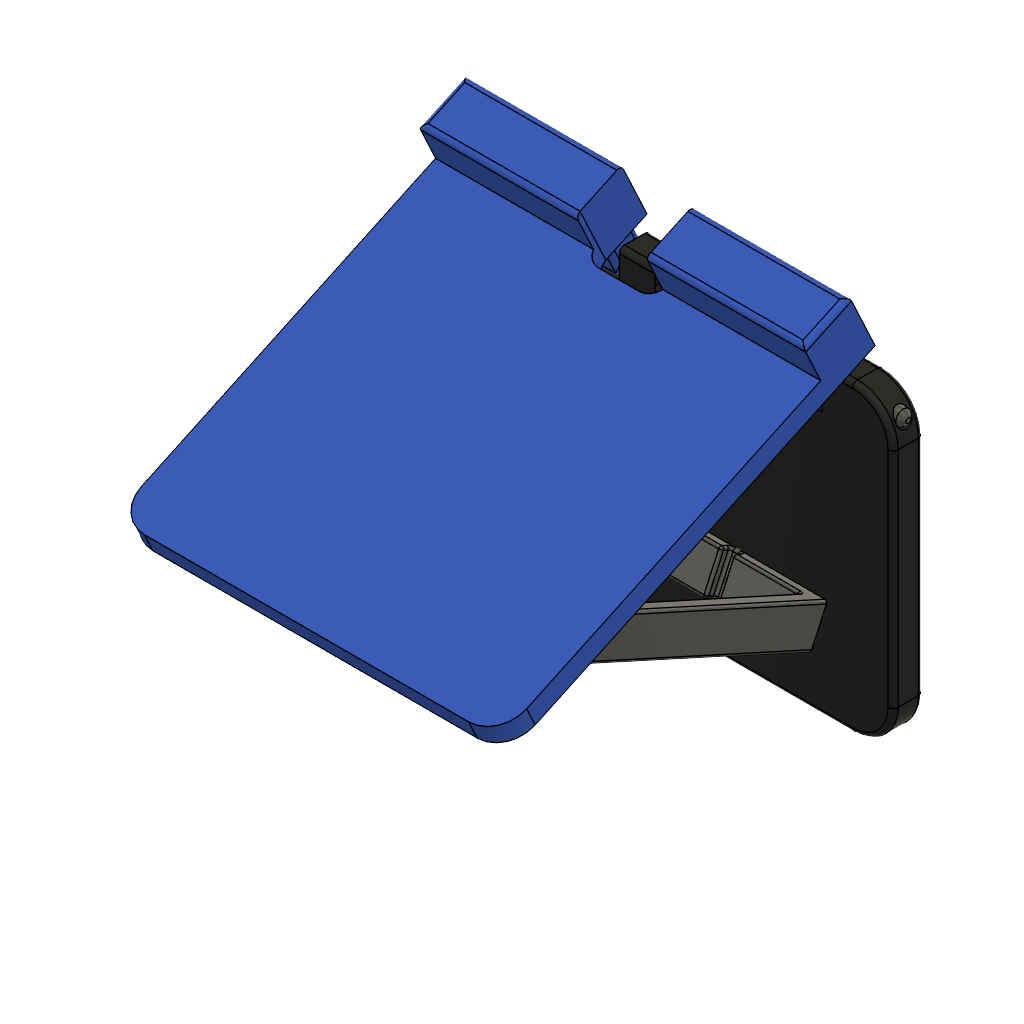
Foldable_Mobile_Stand (Autodesk Fusion 360 design; units mm, degrees)
part number: 2026-11-21-18-16-52-364
part number: 2026-11-21-19-07-08-152
part number: 2026-11-21-19-07-08-221
part number: 2026-11-21-19-07-08-273
part number: 2026-11-21-19-07-08-337
part number: 2026-11-21-19-07-08-382
Autodesk Fusion 360 part; units mm, degrees
sketch "Base Outline" plane through (0, 0, 0) normal (0, 0, 1) x (1, 0, 0)
  line L0 (0, 0) -> (80, 0)
  line L1 (80, 0) -> (80, 60)
  line L2 (80, 60) -> (0, 60)
  line L3 (0, 60) -> (0, 0)
  dimension "d9" = 80
  dimension "d10" = 60
  constraint coincident L0.start L3.end
  measures "d9" horizontal distance of L0.start L0.end
  measures "d10" vertical distance of L0.end L1.end
extrude "Base Box" add sketch "Base Outline" along normal blind 6 makes body 1
fillet "Vertical Corner Fillets" radius 8 4 edges at (0, 60, 3) (80, 60, 3) (80, 0, 3) (0, 0, 3) on bodies 1
fillet "Top Bottom Edge Fillets" radius 1 128 edges at (2.3431, 2.3431, 6) (0, 30, 6) (2.3431, 57.6569, 6) (40, 60, 6) (77.6569, 57.6569, 6) (80, 30, 6) (77.6569, 2.3431, 6) (40, 0, 6) (40, 0, 6) (77.6569, 2.3431, 6) (80, 30, 6) (77.6569, 57.6569, 6) (40, 60, 6) (2.3431, 57.6569, 6) (0, 30, 6) (2.3431, 2.3431, 6) (77.6569, 2.3431, 6) (40, 0, 6) (2.3431, 2.3431, 6) (0, 30, 6) (2.3431, 57.6569, 6) (40, 60, 6) (77.6569, 57.6569, 6) (80, 30, 6) (80, 30, 6) (77.6569, 57.6569, 6) (40, 60, 6) (2.3431, 57.6569, 6) (0, 30, 6) (2.3431, 2.3431, 6) (40, 0, 6) (77.6569, 2.3431, 6) (77.6569, 57.6569, 6) (80, 30, 6) (77.6569, 2.3431, 6) (40, 0, 6) (2.3431, 2.3431, 6) (0, 30, 6) (2.3431, 57.6569, 6) (40, 60, 6) (40, 60, 6) (2.3431, 57.6569, 6) (0, 30, 6) (2.3431, 2.3431, 6) (40, 0, 6) (77.6569, 2.3431, 6) (80, 30, 6) (77.6569, 57.6569, 6) (2.3431, 57.6569, 6) (40, 60, 6) (77.6569, 57.6569, 6) (80, 30, 6) (77.6569, 2.3431, 6) (40, 0, 6) (2.3431, 2.3431, 6) (0, 30, 6) (0, 30, 6) (2.3431, 2.3431, 6) (40, 0, 6) (77.6569, 2.3431, 6) (80, 30, 6) (77.6569, 57.6569, 6) (40, 60, 6) (2.3431, 57.6569, 6) (2.3431, 2.3431, 0) (40, 0, 0) (77.6569, 2.3431, 0) (80, 30, 0) (77.6569, 57.6569, 0) (40, 60, 0) (2.3431, 57.6569, 0) (0, 30, 0) (0, 30, 0) (2.3431, 2.3431, 0) (40, 0, 0) (77.6569, 2.3431, 0) (80, 30, 0) (77.6569, 57.6569, 0) (40, 60, 0) (2.3431, 57.6569, 0) (2.3431, 57.6569, 0) (0, 30, 0) (2.3431, 2.3431, 0) (40, 0, 0) (77.6569, 2.3431, 0) (80, 30, 0) (77.6569, 57.6569, 0) (40, 60, 0) (40, 60, 0) (2.3431, 57.6569, 0) (0, 30, 0) (2.3431, 2.3431, 0) (40, 0, 0) (77.6569, 2.3431, 0) (80, 30, 0) (77.6569, 57.6569, 0) (77.6569, 57.6569, 0) (40, 60, 0) (2.3431, 57.6569, 0) (0, 30, 0) (2.3431, 2.3431, 0) (40, 0, 0) (77.6569, 2.3431, 0) (80, 30, 0) (80, 30, 0) (77.6569, 57.6569, 0) (40, 60, 0) (2.3431, 57.6569, 0) (0, 30, 0) (2.3431, 2.3431, 0) (40, 0, 0) (77.6569, 2.3431, 0) (77.6569, 2.3431, 0) (80, 30, 0) (77.6569, 57.6569, 0) (40, 60, 0) (2.3431, 57.6569, 0) (0, 30, 0) (2.3431, 2.3431, 0) (40, 0, 0) (40, 0, 0) (77.6569, 2.3431, 0) (80, 30, 0) (77.6569, 57.6569, 0) (40, 60, 0) (2.3431, 57.6569, 0) (0, 30, 0) (2.3431, 2.3431, 0) on bodies 1
sketch "Rear Slots" plane through (0, 0, 0) normal (0, 0, 1) x (1, 0, 0)
  line L0 (14, 52) -> (26, 52)
  line L1 (26, 52) -> (26, 63)
  line L2 (26, 63) -> (14, 63)
  line L3 (14, 63) -> (14, 52)
  line L4 (54, 52) -> (66, 52)
  line L5 (66, 52) -> (66, 63)
  line L6 (66, 63) -> (54, 63)
  line L7 (54, 63) -> (54, 52)
extrude "Rear Slots Cut" cut sketch "Rear Slots" along normal through all bodies 1
sketch "Cable Notch" plane through (0, 0, 0) normal (0, 0, 1) x (1, 0, 0)
  line L0 (33, 63) -> (33, 57)
  arc A0 (33, 57) -> (36, 54) centre (36.0011, 57.0011) ccw
  line L1 (36, 54) -> (44, 54)
  arc A1 (44, 54) -> (47, 57) centre (43.9989, 57.0011) ccw
  line L2 (47, 57) -> (47, 63)
  line L3 (47, 63) -> (33, 63)
extrude "Cable Notch Cut" cut sketch "Cable Notch" along normal through all bodies 1
sketch "Hinge Pin Hole" plane through (0, 0, 0) normal (1, 0, 0) x (0, 0, -1)
  circle A0 centre (-3, 56) radius 1.6
  dimension "d19" = 3.2
  measures "d19" diameter of A0
extrude "Hinge Pin Hole Cut" cut sketch "Hinge Pin Hole" against normal through all bodies 1
sketch "Bottom Recesses" plane through (0, 0, 0) normal (0, 0, 1) x (1, 0, 0)
  circle A0 centre (12, 12) radius 5
  circle A1 centre (68, 12) radius 5
  circle A2 centre (12, 46) radius 5
  circle A3 centre (68, 46) radius 5
  dimension "d21" = 10
  dimension "d22" = 10
  dimension "d23" = 10
  dimension "d24" = 10
  measures "d21" diameter of A0
  measures "d22" diameter of A1
  measures "d23" diameter of A2
  measures "d24" diameter of A3
extrude "Bottom Recesses Cut" cut sketch "Bottom Recesses" along normal blind 1 bodies 1
ref_plane "WorkPlane1" through (0, 80, 0) normal (0, 1, 0) x (0, 0, 1)
sketch "BackSupport Plate" plane through (0, 80, 0) normal (0, 1, 0) x (1, 0, 0)
  line L0 (0, 0) -> (76, 0)
  line L1 (76, 0) -> (76, -80)
  line L2 (76, -80) -> (0, -80)
  line L3 (0, -80) -> (0, 0)
extrude "Plate Extrude" add sketch "BackSupport Plate" along normal blind 4 separate body makes body 2
fillet "Top Corner Fillets" radius 6 2 edges at (0, 82, 80) (76, 82, 80) on bodies 2
sketch "Phone Lip" plane through (0, 0, 0) normal (0, 0, 1) x (1, 0, 0)
  line L0 (0, 72) -> (76, 72)
  line L1 (76, 72) -> (76, 81)
  line L2 (76, 81) -> (0, 81)
  line L3 (0, 81) -> (0, 72)
extrude "Phone Lip Extrude" add sketch "Phone Lip" along normal blind 10 bodies 2
fillet "Lip Fillets" radius 1 4 edges at (38, 72, 0) (76, 72, 5) (38, 72, 10) (0, 72, 5) on bodies 2
ref_plane "WorkPlane2" through (14.2, 0, 0) normal (1, 0, 0) x (0, 1, 0)
sketch "Knuckle 1" plane through (14.2, 0, 0) normal (1, 0, 0) x (0, 0, -1)
  circle A0 centre (-2.8, 82) radius 2.8
  dimension "d39" = 5.6
  measures "d39" diameter of A0
extrude "Knuckle 1 (1)" add sketch "Knuckle 1" along normal blind 11.6 bodies 2
sketch "Knuckle Bore 1" plane through (14.2, 0, 0) normal (1, 0, 0) x (0, 0, -1)
  circle A0 centre (-2.8, 82) radius 1.6
  dimension "d42" = 3.2
  measures "d42" diameter of A0
extrude "Knuckle Bore 1 (1)" cut sketch "Knuckle Bore 1" along normal blind 11.6 bodies 2
ref_plane "WorkPlane3" through (54.2, 0, 0) normal (1, 0, 0) x (0, 1, 0)
sketch "Knuckle 2" plane through (54.2, 0, 0) normal (1, 0, 0) x (0, 0, -1)
  circle A0 centre (-2.8, 82) radius 2.8
  dimension "d47" = 5.6
  measures "d47" diameter of A0
extrude "Knuckle 2 (1)" add sketch "Knuckle 2" along normal blind 11.6 bodies 2
sketch "Knuckle Bore 2" plane through (54.2, 0, 0) normal (1, 0, 0) x (0, 0, -1)
  circle A0 centre (-2.8, 82) radius 1.6
  dimension "d50" = 3.2
  measures "d50" diameter of A0
extrude "Knuckle Bore 2 (1)" cut sketch "Knuckle Bore 2" along normal blind 11.6 bodies 2
ref_plane "WorkPlane4" through (17, 0, 0) normal (1, 0, 0) x (0, 1, 0)
sketch "Pivot Lug 1" plane through (17, 0, 0) normal (1, 0, 0) x (0, 0, -1)
  line L0 (-56, 83) -> (-64, 83)
  line L1 (-64, 83) -> (-64, 92)
  line L2 (-64, 92) -> (-56, 92)
  line L3 (-56, 92) -> (-56, 83)
extrude "Pivot Lug 1 (1)" add sketch "Pivot Lug 1" along normal blind 6 bodies 2
sketch "Pivot Lug Hole 1" plane through (17, 0, 0) normal (1, 0, 0) x (0, 0, -1)
  circle A0 centre (-60, 88) radius 1.6
  dimension "d57" = 3.2
  measures "d57" diameter of A0
extrude "Pivot Lug Hole 1 (1)" cut sketch "Pivot Lug Hole 1" along normal blind 6 bodies 2
ref_plane "WorkPlane5" through (57, 0, 0) normal (1, 0, 0) x (0, 1, 0)
sketch "Pivot Lug 2" plane through (57, 0, 0) normal (1, 0, 0) x (0, 0, -1)
  line L0 (-56, 83) -> (-64, 83)
  line L1 (-64, 83) -> (-64, 92)
  line L2 (-64, 92) -> (-56, 92)
  line L3 (-56, 92) -> (-56, 83)
extrude "Pivot Lug 2 (1)" add sketch "Pivot Lug 2" along normal blind 6 bodies 2
sketch "Pivot Lug Hole 2" plane through (57, 0, 0) normal (1, 0, 0) x (0, 0, -1)
  circle A0 centre (-60, 88) radius 1.6
  dimension "d64" = 3.2
  measures "d64" diameter of A0
extrude "Pivot Lug Hole 2 (1)" cut sketch "Pivot Lug Hole 2" along normal blind 6 bodies 2
ref_plane "WorkPlane6" through (0, 70, 0) normal (0, 1, 0) x (0, 0, 1)
sketch "Cable Gap" plane through (0, 70, 0) normal (0, 1, 0) x (1, 0, 0)
  line L0 (31, 1) -> (31, -9)
  arc A0 (31, -9) -> (34, -12) centre (34.0001, -8.9999) ccw
  line L1 (34, -12) -> (42, -12)
  arc A1 (42, -12) -> (45, -9) centre (41.9999, -8.9999) ccw
  line L2 (45, -9) -> (45, 1)
  line L3 (45, 1) -> (31, 1)
extrude "Cable Gap Cut" cut sketch "Cable Gap" along normal blind 25 bodies 2
sketch "HingePin Sketch" plane through (0, 0, 0) normal (1, 0, 0) x (0, 0, -1)
  circle A0 centre (-1.5, 130) radius 1.5
  dimension "d71" = 3
  measures "d71" diameter of A0
extrude "HingePin Extrude" add sketch "HingePin Sketch" along normal blind 80 separate body makes body 3
chamfer "HingePin End Chamfers" distance 1 angle 45 2 edges at (80, 129.4576, 2.8985) (0, 129.4576, 2.8985) on bodies 3
sketch "StrutPin Sketch" plane through (0, 0, 0) normal (1, 0, 0) x (0, 0, -1)
  circle A0 centre (-1.5, 215) radius 1.5
  dimension "d81" = 3
  measures "d81" diameter of A0
extrude "StrutPin Extrude" add sketch "StrutPin Sketch" along normal blind 70 separate body makes body 4
chamfer "StrutPin End Chamfers" distance 1 angle 45 2 edges at (70, 214.4576, 2.8985) (0, 214.4576, 2.8985) on bodies 4
sketch "AngleSupport Sketch" plane through (0, 0, 0) normal (0, 0, 1) x (1, 0, 0)
  line L0 (0, 140) -> (65, 140)
  line L1 (65, 140) -> (65, 196)
  arc A0 (65, 196) -> (57, 196) centre (61, 196) ccw
  line L2 (57, 196) -> (57, 148)
  line L3 (57, 148) -> (43.5, 148)
  line L4 (43.5, 148) -> (43.5, 146)
  line L5 (43.5, 146) -> (41.5, 146)
  line L6 (41.5, 146) -> (41.5, 148)
  line L7 (41.5, 148) -> (33.5, 148)
  line L8 (33.5, 148) -> (33.5, 146)
  line L9 (33.5, 146) -> (31.5, 146)
  line L10 (31.5, 146) -> (31.5, 148)
  line L11 (31.5, 148) -> (23.5, 148)
  line L12 (23.5, 148) -> (23.5, 146)
  line L13 (23.5, 146) -> (21.5, 146)
  line L14 (21.5, 146) -> (21.5, 148)
  line L15 (21.5, 148) -> (8, 148)
  line L16 (8, 148) -> (8, 196)
  arc A1 (8, 196) -> (0, 196) centre (4, 196) ccw
  line L17 (0, 196) -> (0, 140)
  line L18 (0, 140) -> (0, 140)
  circle A2 centre (4, 196) radius 1.6
  circle A3 centre (61, 196) radius 1.6
  dimension "d85" = 3.2
  dimension "d86" = 3.2
  measures "d85" diameter of A2
  measures "d86" diameter of A3
extrude "AngleSupport Extrude" add sketch "AngleSupport Sketch" along normal blind 3 separate body makes body 5
fillet "AngleSupport Edge Fillets" radius 0.5 84 edges at (2.5083, 196.5786, 3) (2.5083, 196.5786, 0) (59.5083, 196.5786, 3) (59.5083, 196.5786, 0) (4, 200, 0) (0, 168, 0) (8, 172, 0) (4, 200, 3) (0, 168, 3) (8, 172, 3) (8, 172, 0) (4, 200, 0) (0, 168, 0) (8, 172, 3) (4, 200, 3) (0, 168, 3) (8, 148, 1.5) (14.75, 148, 0) (14.75, 148, 3) (21.5, 148, 1.5) (21.5, 147, 0) (21.5, 147, 3) (21.5, 146, 1.5) (22.5, 146, 0) (22.5, 146, 3) (23.5, 146, 1.5) (23.5, 147, 0) (23.5, 147, 3) (23.5, 148, 1.5) (27.5, 148, 0) (27.5, 148, 3) (31.5, 148, 1.5) (31.5, 147, 0) (31.5, 147, 3) (31.5, 146, 1.5) (32.5, 146, 0) (32.5, 146, 3) (33.5, 146, 1.5) (33.5, 147, 0) (33.5, 147, 3) (33.5, 148, 1.5) (37.5, 148, 0) (37.5, 148, 3) (41.5, 148, 1.5) (41.5, 147, 0) (41.5, 147, 3) (41.5, 146, 1.5) (42.5, 146, 0) (42.5, 146, 3) (43.5, 146, 1.5) (43.5, 147, 0) (43.5, 147, 3) (43.5, 148, 1.5) (50.25, 148, 0) (50.25, 148, 3) (57, 148, 1.5) (57, 172, 0) (61, 200, 0) (65, 168, 0) (57, 172, 3) (61, 200, 3) (65, 168, 3) (61, 200, 0) (57, 172, 0) (65, 168, 0) (61, 200, 3) (57, 172, 3) (65, 168, 3) (65, 168, 0) (61, 200, 0) (57, 172, 0) (65, 168, 3) (61, 200, 3) (57, 172, 3) (65, 140, 1.5) (32.5, 140, 0) (32.5, 140, 3) (0, 140, 1.5) (0, 168, 0) (4, 200, 0) (8, 172, 0) (0, 168, 3) (4, 200, 3) (8, 172, 3) on bodies 5
copy_body "Body->Comp1" bodies 1 removing the originals makes body 6 in component "Base"
copy_body "Body->Comp2" bodies 2 removing the originals makes body 7 in component "BackSupport"
copy_body "Body->Comp3" bodies 5 removing the originals makes body 8 in component "AngleSupport"
copy_body "Body->Comp4" bodies 3 removing the originals makes body 9 in component "HingePin"
copy_body "Body->Comp5" bodies 4 removing the originals makes body 10 in component "StrutPin"
ref_plane "WorkPlane1" through (0, 0, 15) normal (0, 0, 1) x (1, 0, 0) in component "BackSupport"
sketch "BS Plate" plane through (0, 0, 15) normal (0, 0, 1) x (1, 0, 0) in component "BackSupport"
  line L0 (0, -21.2) -> (76, -21.2)
  line L1 (76, -21.2) -> (76, 58.8)
  line L2 (76, 58.8) -> (0, 58.8)
  line L3 (0, 58.8) -> (0, -21.2)
extrude "BS Plate Extrude" add sketch "BS Plate" along normal blind 4 separate body makes body 11 in component "BackSupport"
fillet "BS Top Corner Fillets" radius 6 2 edges at (76, -21.2, 17) (0, -21.2, 17) on bodies 11 in component "BackSupport"
ref_plane "WorkPlane2" through (0, 0, 19) normal (0, 0, 1) x (1, 0, 0) in component "BackSupport"
sketch "BS Phone Lip" plane through (0, 0, 19) normal (0, 0, 1) x (1, 0, 0) in component "BackSupport"
  line L0 (0, 48.8) -> (76, 48.8)
  line L1 (76, 48.8) -> (76, 58.8)
  line L2 (76, 58.8) -> (0, 58.8)
  line L3 (0, 58.8) -> (0, 48.8)
extrude "BS Phone Lip Extrude" add sketch "BS Phone Lip" along normal blind 8 bodies 11 in component "BackSupport"
fillet "BS Lip Fillets" radius 1 4 edges at (0, 53.8, 27) (38, 48.8, 27) (76, 53.8, 27) (38, 58.8, 27) on bodies 11 in component "BackSupport"
ref_plane "WorkPlane3" through (0, 0, 3) normal (0, 0, 1) x (1, 0, 0) in component "BackSupport"
sketch "BS Bridge Blocks" plane through (0, 0, 3) normal (0, 0, 1) x (1, 0, 0) in component "BackSupport"
  line L0 (14.2, 53.2) -> (25.8, 53.2)
  line L1 (25.8, 53.2) -> (25.8, 58.8)
  line L2 (25.8, 58.8) -> (14.2, 58.8)
  line L3 (14.2, 58.8) -> (14.2, 53.2)
  line L4 (54.2, 53.2) -> (65.8, 53.2)
  line L5 (65.8, 53.2) -> (65.8, 58.8)
  line L6 (65.8, 58.8) -> (54.2, 58.8)
  line L7 (54.2, 58.8) -> (54.2, 53.2)
extrude "BS Bridge Blocks Extrude" add sketch "BS Bridge Blocks" along normal blind 13 bodies 11 in component "BackSupport"
fillet "BS Bridge Fillets" radius 1 8 edges at (54.2, 58.8, 9) (54.2, 53.2, 9) (65.8, 53.2, 9) (65.8, 58.8, 9) (14.2, 53.2, 9) (25.8, 53.2, 9) (14.2, 58.8, 9) (25.8, 58.8, 9) on bodies 11 in component "BackSupport"
ref_plane "WorkPlane4" through (14.2, 0, 0) normal (1, 0, 0) x (0, 1, 0) in component "BackSupport"
sketch "BS Knuckle 1" plane through (14.2, 0, 0) normal (1, 0, 0) x (0, 0, -1) in component "BackSupport"
  circle A0 centre (-3, 56) radius 2.8
  dimension "d111" = 5.6
  measures "d111" diameter of A0
extrude "BS Knuckle 1 (1)" add sketch "BS Knuckle 1" along normal blind 11.6 bodies 11 in component "BackSupport"
sketch "BS Knuckle Bore 1" plane through (14.2, 0, 0) normal (1, 0, 0) x (0, 0, -1) in component "BackSupport"
  circle A0 centre (-3, 56) radius 1.6
  dimension "d114" = 3.2
  measures "d114" diameter of A0
extrude "BS Knuckle Bore 1 (1)" cut sketch "BS Knuckle Bore 1" along normal blind 11.6 bodies 11 in component "BackSupport"
ref_plane "WorkPlane5" through (54.2, 0, 0) normal (1, 0, 0) x (0, 1, 0) in component "BackSupport"
sketch "BS Knuckle 2" plane through (54.2, 0, 0) normal (1, 0, 0) x (0, 0, -1) in component "BackSupport"
  circle A0 centre (-3, 56) radius 2.8
  dimension "d119" = 5.6
  measures "d119" diameter of A0
extrude "BS Knuckle 2 (1)" add sketch "BS Knuckle 2" along normal blind 11.6 bodies 11 in component "BackSupport"
sketch "BS Knuckle Bore 2" plane through (54.2, 0, 0) normal (1, 0, 0) x (0, 0, -1) in component "BackSupport"
  circle A0 centre (-3, 56) radius 1.6
  dimension "d122" = 3.2
  measures "d122" diameter of A0
extrude "BS Knuckle Bore 2 (1)" cut sketch "BS Knuckle Bore 2" along normal blind 11.6 bodies 11 in component "BackSupport"
ref_plane "WorkPlane6" through (0, 0, 9) normal (0, 0, 1) x (1, 0, 0) in component "BackSupport"
sketch "BS Pivot Lugs" plane through (0, 0, 9) normal (0, 0, 1) x (1, 0, 0) in component "BackSupport"
  line L0 (16, -5.2) -> (24, -5.2)
  line L1 (24, -5.2) -> (24, 2.8)
  line L2 (24, 2.8) -> (16, 2.8)
  line L3 (16, 2.8) -> (16, -5.2)
  line L4 (56, -5.2) -> (64, -5.2)
  line L5 (64, -5.2) -> (64, 2.8)
  line L6 (64, 2.8) -> (56, 2.8)
  line L7 (56, 2.8) -> (56, -5.2)
extrude "BS Pivot Lugs Extrude" add sketch "BS Pivot Lugs" along normal blind 7 bodies 11 in component "BackSupport"
sketch "BS Pivot Lug Hole" plane through (0, 0, 0) normal (1, 0, 0) x (0, 0, -1) in component "BackSupport"
  circle A0 centre (-12, -1.2) radius 1.6
  dimension "d129" = 3.2
  measures "d129" diameter of A0
extrude "BS Pivot Lug Hole Cut" cut sketch "BS Pivot Lug Hole" against normal through all bodies 11 in component "BackSupport"
ref_plane "WorkPlane7" through (0, 0, 10) normal (0, 0, 1) x (1, 0, 0) in component "BackSupport"
sketch "BS Cable Gap" plane through (0, 0, 10) normal (0, 0, 1) x (1, 0, 0) in component "BackSupport"
  line L0 (31, 60) -> (31, 49.8)
  arc A0 (31, 49.8) -> (34, 46.8) centre (34.0001, 49.8001) ccw
  line L1 (34, 46.8) -> (42, 46.8)
  arc A1 (42, 46.8) -> (45, 49.8) centre (41.9999, 49.8001) ccw
  line L2 (45, 49.8) -> (45, 60)
  line L3 (45, 60) -> (31, 60)
extrude "BS Cable Gap Cut" cut sketch "BS Cable Gap" along normal blind 20 bodies 11 in component "BackSupport"
delete_body "RemoveBody1" bodies 7 in component "BackSupport"
delete_body "RemoveBody1'" bodies 8 in component "AngleSupport"
ref_plane "WorkPlane1" through (12.5, 0, 0) normal (1, 0, 0) x (0, 1, 0) in component "AngleSupport"
sketch "AS Arm Profile 12.5" plane through (12.5, 0, 0) normal (1, 0, 0) x (0, 0, -1) in component "AngleSupport"
  line L0 (0, 144) -> (0, 200)
  line L1 (0, 200) -> (-8, 200)
  line L2 (-8, 200) -> (-8, 144)
  arc A0 (-8, 144) -> (0, 144) centre (-4, 144) ccw
  circle A1 centre (-4, 144) radius 1.6
extrude "AS Arm Extrude 12.5" add sketch "AS Arm Profile 12.5" along normal blind 3 separate body makes body 12 in component "AngleSupport"
ref_plane "WorkPlane2" through (64.5, 0, 0) normal (1, 0, 0) x (0, 1, 0) in component "AngleSupport"
sketch "AS Arm Profile 64.5" plane through (64.5, 0, 0) normal (1, 0, 0) x (0, 0, -1) in component "AngleSupport"
  line L0 (0, 144) -> (0, 200)
  line L1 (0, 200) -> (-8, 200)
  line L2 (-8, 200) -> (-8, 144)
  arc A0 (-8, 144) -> (0, 144) centre (-4, 144) ccw
  circle A1 centre (-4, 144) radius 1.6
extrude "AS Arm Extrude 64.5" add sketch "AS Arm Profile 64.5" along normal blind 3 separate body makes body 13 in component "AngleSupport"
sketch "AS Crossbar" plane through (0, 0, 0) normal (0, 0, 1) x (1, 0, 0) in component "AngleSupport"
  line L0 (12.5, 197) -> (67.5, 197)
  line L1 (67.5, 197) -> (67.5, 200)
  line L2 (67.5, 200) -> (12.5, 200)
  line L3 (12.5, 200) -> (12.5, 197)
extrude "AS Crossbar Extrude" add sketch "AS Crossbar" along normal blind 8 bodies 12 13 in component "AngleSupport"
sketch "AS Notches" plane through (0, 0, 0) normal (0, 0, 1) x (1, 0, 0) in component "AngleSupport"
  line L0 (29, 196) -> (31, 196)
  line L1 (31, 196) -> (31, 199)
  line L2 (31, 199) -> (29, 199)
  line L3 (29, 199) -> (29, 196)
  line L4 (39, 196) -> (41, 196)
  line L5 (41, 196) -> (41, 199)
  line L6 (41, 199) -> (39, 199)
  line L7 (39, 199) -> (39, 196)
  line L8 (49, 196) -> (51, 196)
  line L9 (51, 196) -> (51, 199)
  line L10 (51, 199) -> (49, 199)
  line L11 (49, 199) -> (49, 196)
extrude "AS Notch Cut" cut sketch "AS Notches" along normal blind 8 bodies 12 in component "AngleSupport"
fillet "AS Edge Fillets" radius 0.5 84 edges at (30, 199, 0) (31, 199, 4) (30, 199, 8) (29, 199, 4) (31, 197, 4) (31, 198, 8) (31, 198, 0) (29, 197, 4) (29, 198, 0) (29, 198, 8) (40, 199, 0) (41, 199, 4) (40, 199, 8) (39, 199, 4) (41, 197, 4) (41, 198, 8) (41, 198, 0) (39, 197, 4) (39, 198, 0) (39, 198, 8) (50, 199, 0) (51, 199, 4) (50, 199, 8) (49, 199, 4) (51, 197, 4) (51, 198, 8) (51, 198, 0) (49, 197, 4) (49, 198, 0) (49, 198, 8) (22.25, 197, 0) (15.5, 170.5, 0) (15.5, 140, 4) (15.5, 170.5, 8) (12.5, 172, 0) (12.5, 140, 4) (12.5, 172, 8) (40, 200, 0) (67.5, 172, 0) (67.5, 140, 4) (67.5, 172, 8) (64.5, 170.5, 0) (64.5, 140, 4) (64.5, 170.5, 8) (57.75, 197, 0) (45, 197, 0) (35, 197, 0) (64.5, 197, 4) (57.75, 197, 8) (45, 197, 8) (22.25, 197, 8) (15.5, 197, 4) (35, 197, 8) (64.5, 140, 4) (64.5, 170.5, 0) (64.5, 170.5, 8) (64.5, 170.5, 8) (64.5, 140, 4) (64.5, 170.5, 0) (64.5, 144.5786, 5.4917) (67.5, 144.5786, 5.4917) (67.5, 140, 4) (67.5, 172, 0) (67.5, 172, 8) (67.5, 172, 8) (67.5, 140, 4) (67.5, 172, 0) (67.5, 200, 4) (40, 200, 8) (12.5, 172, 8) (12.5, 140, 4) (12.5, 172, 0) (15.5, 170.5, 8) (15.5, 140, 4) (15.5, 170.5, 0) (12.5, 140, 4) (12.5, 172, 0) (12.5, 172, 8) (12.5, 200, 4) (12.5, 144.5786, 5.4917) (15.5, 144.5786, 5.4917) (15.5, 140, 4) (15.5, 170.5, 0) (15.5, 170.5, 8) on bodies 12 in component "AngleSupport"
delete_body "RemoveBody1''" bodies 10 in component "StrutPin"
ref_plane "WorkPlane1" through (10, 0, 0) normal (1, 0, 0) x (0, 1, 0) in component "StrutPin"
sketch "SP Pin Profile" plane through (10, 0, 0) normal (1, 0, 0) x (0, 0, -1) in component "StrutPin"
  circle A0 centre (-1.5, 215) radius 1.5
extrude "SP Pin Extrude" add sketch "SP Pin Profile" along normal blind 60 separate body makes body 14 in component "StrutPin"
chamfer "SP End Chamfers" distance 1 angle 45 2 edges at (70, 214.4576, 2.8985) (10, 214.4576, 2.8985) on bodies 14 in component "StrutPin"
component "Base" placed x (1, 0, 0) y (0, 1, 0) z (0, 0, 1) at (0, 0, 0)
component "BackSupport" placed x (1, 0, 0) y (0, 1, 0) z (0, 0, 1) at (0, 0, 0)
component "AngleSupport" placed x (1, 0, 0) y (0, 1, 0) z (0, 0, 1) at (0, 0, 0)
component "HingePin" placed x (1, 0, 0) y (0, 1, 0) z (0, 0, 1) at (0, 0, 0)
component "StrutPin" placed x (1, 0, 0) y (0, 1, 0) z (0, 0, 1) at (0, 0, 0)
equation "BoxX = 80 mm"
equation "BoxY = 60 mm"
equation "Thick = 6 mm"
equation "CornerR = 8 mm"
equation "EdgeR = 1 mm"
equation "PinDia = 3.2 mm"
equation "PadDia = 10 mm"
equation "PadDepth = 1 mm"
equation "d9 = BoxX"
equation "d10 = BoxY"
equation "d11 = Thick"
equation "d14 = CornerR"
equation "d16 = EdgeR"
equation "d19 = PinDia"
equation "d21 = PadDia"
equation "d22 = PadDia"
equation "d23 = PadDia"
equation "d24 = PadDia"
equation "d25 = PadDepth"
named bodies: "Base", "BackSupport", "HingePin", "StrutPin", "AngleSupport"
